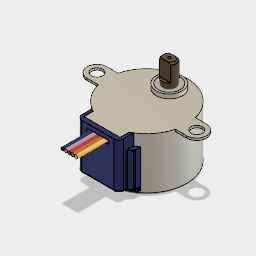
_28BYJ-48+Stepper+Motor.dbc9e391-d2c8-433e-843d-24143737a80f (Autodesk Fusion 360 design; units mm, degrees)
Autodesk Fusion 360 part; units mm, degrees
sketch "24BYJ-48 Step Motor" plane through (0, 0, 0) normal (0, 1, 0) x (1, 0, 0) in component "28BYJ-48 Stepper Motor"
  line L0 (0, 0) -> (0, 7.8573) construction
  circle A0 centre (0, 7.8573) radius 2.5
  circle A1 centre (0, 7.8573) radius 4.6
  line L1 (-2, 9.3573) -> (2, 9.3573)
  line L2 (2, 6.3573) -> (-2, 6.3573)
  circle A2 centre (17.5, -0.0114) radius 2
  arc A3 (17.5, -3.5114) -> (17.5, 3.4886) centre (17.5, -0.0114) ccw
  circle A4 centre (-17.5, -0.0114) radius 2
  arc A5 (-17.5, 3.4886) -> (-17.5, -3.5114) centre (-17.5, -0.0114) ccw
  line L3 (17.5, 3.4886) -> (13.5584, 3.4886)
  line L4 (17.5, -3.5114) -> (13.5525, -3.5114)
  line L5 (-17.5, 3.4886) -> (-13.5584, 3.4886)
  line L6 (-17.5, -3.5114) -> (-13.5525, -3.5114)
  line L7 (-6.3, -12.5024) -> (-6.3, -15.6927)
  line L8 (6.3, -12.5024) -> (6.3, -15.6927)
  line L9 (6.3, -15.6927) -> (-6.3, -15.6927)
  line L10 (7.35, -11.9154) -> (7.35, -15.5438)
  line L11 (5.6511, -17.2427) -> (-5.6511, -17.2427)
  line L12 (-7.35, -15.5438) -> (-7.35, -11.9154)
  arc A6 (-7.35, -15.5438) -> (-5.6511, -17.2427) centre (-5.6511, -15.5438) ccw
  arc A7 (5.6511, -17.2427) -> (7.35, -15.5438) centre (5.6511, -15.5438) ccw
  line L13 (7.35, -14.45) -> (8.75, -13.05)
  line L14 (8.75, -13.05) -> (8.75, -10.9287)
  line L15 (-7.35, -14.45) -> (-8.75, -13.05)
  line L16 (-8.75, -13.05) -> (-8.75, -10.9287)
  line L17 (21, -0.0114) -> (21, 13.9573) construction
  line L18 (-21, -0.0114) -> (-21, 13.9573) construction
  line L19 (21, 13.9573) -> (-21, 13.9573) construction
  circle A8 centre (0, 7.8573) radius 3.85
  line L20 (-6.4707, 3.2573) -> (8.5293, 3.2573) construction
  circle A9 centre (0, 0) radius 14
  arc A10 (-8.75, -11.5623) -> (8.75, -11.5623) centre (0, 0) ccw
  line L21 (-1.5, -14.4222) -> (-1.5, -13.9194)
  line L22 (1.5, -14.4222) -> (1.5, -13.9194)
  dimension "d2" = 3
  dimension "d3" = 5
  dimension "d4" = 3.5
  dimension "d6" = 4
  dimension "d11" = 45
  dimension "d12" = 14.7
  dimension "d14" = 17.5
  dimension "d15" = 12.6
  dimension "d16" = 1.55
  dimension "d17" = 42
  dimension "d18" = 31.2
  dimension "d19" = 9.2
  dimension "d20" = 7.7
  dimension "d21" = 10.7
  dimension "d26" = 28
  dimension "d49" = 14.5
  dimension "d53" = 3
  measures "d2" distance of L1 L2
  measures "d3" diameter of A0
  measures "d4" radius of A3
  measures "d6" diameter of A2
  measures "d11" angle of L10 L13
  measures "d12" distance of L10 L12
  measures "d14" distance of L14 L16
  measures "d15" distance of L7.end L8.end
  measures "d16" distance of L9 L11
  measures "d17" distance of L17 L18
  measures "d18" distance of L11 L19
  measures "d19" diameter of A1
  measures "d20" diameter of A8
  measures "d21" distance of L19 L20
  measures "d26" diameter of A9
  measures "d49" radius of A10
  measures "d53" distance of L21 L22
extrude "Extrude1" add sketch "24BYJ-48 Step Motor" against normal blind 0.75 contours A0 L1 L2 | A0 L1 | A0 L2 | A1 | A3 L3 L4 A9 | A9 | A5 L5 L6 A9 | L8 A9 A10 L22 | L7 L8 L9 A10 | A9 A10 L21 L22 | L7 A9 A10 L21 | A8 makes body 1 in component "Metal Case"
extrude "Extrude2" add sketch "24BYJ-48 Step Motor" against normal blind 19 contours A0 L1 L2 | A0 L1 | A0 L2 | A1 | A9 | A8 bodies 1 in component "Metal Case"
extrude "Extrude3" add sketch "24BYJ-48 Step Motor" along normal blind 1.5 contours A1 bodies 1 in component "Metal Case"
extrude "Extrude1'" add sketch "24BYJ-48 Step Motor" along normal blind 1.5 separate body contours A0 L1 L2 | A0 L1 | A0 L2 | A8 makes body 2 in component "Plastic Base"
extrude "Extrude1''" add sketch "24BYJ-48 Step Motor" along normal blind 3.3 separate body contours A0 L1 L2 | A0 L1 | A0 L2 makes body 3 in component "Metal Rod"
extrude "Extrude2'" add sketch "24BYJ-48 Step Motor" along normal blind 9.3 contours A0 L1 L2 bodies 3 in component "Metal Rod"
extrude "Extrude1'''" add sketch "24BYJ-48 Step Motor" against normal blind 16.5 separate body contours L8 L10 A9 A10 | L7 L8 L9 L10 L11 L12 A6 A7 A10 | L7 L12 A9 A10 makes body 4 in component "Plastic Side"
extrude "Extrude2''" add sketch "24BYJ-48 Step Motor" against normal blind 15.7 from surface at -0.8 contours L8 A9 A10 L22 | L7 L8 L9 A10 | A9 A10 L21 L22 | L7 A9 A10 L21 bodies 4 in component "Plastic Side"
extrude "Extrude3'" add sketch "24BYJ-48 Step Motor" against normal blind 12.5 from surface at -4 contours L10 L14 A9 A10 | L10 L13 L14 A10 | L12 L16 A9 A10 | L12 L15 L16 A10 bodies 4 in component "Plastic Side"
extrude "Extrude4" add sketch "24BYJ-48 Step Motor" against normal blind 1 from surface at -16.5 contours L10 L14 A9 A10 | L8 L10 A9 A10 | L8 A9 A10 L22 | L12 L16 A9 A10 | A9 A10 L21 L22 | L7 L12 A9 A10 | L7 A9 A10 L21 bodies 4 in component "Plastic Side"
fillet "Fillet1" radius 0.5 4 edges at (8.75, -10.25, 13.05) (8.75, -17, 11.5623) (-8.75, -17, 11.5623) (-8.75, -10.25, 13.05) on bodies 4 in component "Plastic Side"
fillet "Fillet3" radius 1 5 edges at (7.35, -16.5, 14.9969) (6.8524, -16.5, 16.7451) (0, -16.5, 17.2427) (-6.8524, -16.5, 16.7451) (-7.35, -16.5, 14.9969) on bodies 4 in component "Plastic Side"
fillet "Fillet4" radius 0.5 10 edges at (8.75, -16.5, 12.0769) (8.7119, -16.5, 13.0342) (7.4768, -16.5, 14.3232) (-7.4768, -16.5, 14.3232) (-8.7119, -16.5, 13.0342) (-8.75, -16.5, 12.0769) (7.0571, -16.2071, 14.7429) (7.35, -9.75, 14.45) (-7.35, -9.75, 14.45) (-7.0571, -16.2071, 14.7429) on bodies 4 in component "Plastic Side"
fillet "Fillet5" radius 0.25 5 edges at (8.75, -17.5, 11.1198) (8.6957, -17.5, 11.5375) (0, -17.5, 14.5) (-8.6957, -17.5, 11.5375) (-8.75, -17.5, 11.1198) on bodies 4 in component "Plastic Side"
fillet "Fillet1'" radius 1 1 edges at (-13.0526, -19, -5.0626) on bodies 1 in component "Metal Case"
sphere "SpherePrimitive1" cut diameter 1 placed x (-1, 0, 0) y (0, 0, 1) z (0, 1, 0) at (0, 9.3, -7.8573) bodies 3 in component "Metal Rod"
sketch "Wires" plane through (0, 0, 17.2427) normal (0, 0, 1) x (1, 0, 0) in component "Wires"
  line L0 (-5.6511, -15.5) -> (5.6511, -15.5)
  line L1 (5.6511, -15.5) -> (5.6511, 0)
  line L2 (5.6511, 0) -> (-5.6511, 0)
  line L3 (-5.6511, 0) -> (-5.6511, -15.5)
  line L4 (0, 0) -> (0, -1.5) construction
  line L5 (3.4, -1.5) -> (-3.4, -1.5)
  line L6 (-3.4, -2.7) -> (3.4, -2.7)
  line L7 (-4, -2.1) -> (4, -2.1) construction
  arc A0 (-3.4, -1.5) -> (-3.4, -2.7) centre (-3.4, -2.1) ccw
  arc A1 (3.4, -2.7) -> (3.4, -1.5) centre (3.4, -2.1) ccw
  circle A2 centre (-2.4, -2.1) radius 0.6
  circle A3 centre (-1.2, -2.1) radius 0.6
  circle A4 centre (0, -2.1) radius 0.6
  circle A5 centre (1.2, -2.1) radius 0.6
  circle A6 centre (2.4, -2.1) radius 0.6
  dimension "d64" = 1.5
  dimension "d66" = 8
  dimension "d67" = 0.6
  measures "d64" distance of L4.start L4.end
  measures "d66" distance of L7.start L7.end
  measures "d67" radius of A1
extrude "Extrude5" cut sketch "Wires" against normal blind 1 contours L5 L6 A1 A6 | L5 A5 A6 | A6 | L5 A4 A5 | A5 | L6 A5 A6 | L5 A3 A4 | A4 | L6 A4 A5 | L5 A2 A3 | A3 | L6 A3 A4 | L5 L6 A0 A2 | A2 | L6 A2 A3 bodies 4 in component "Plastic Side"
extrude "Extrude1''''" add sketch "Wires" along normal blind 10 and the other way blind 1 separate body contours A6 | A5 | A4 | A3 | A2 makes body 5 at (-2.4597, -1.503, 20.2427) in component "Wires"
chamfer "Chamfer1" distance 0.5 angle 45 2 edges at (-2.5, 9.3, -7.8573) (2.5, 9.3, -7.8573) on bodies 3 in component "Metal Rod"
component "28BYJ-48 Stepper Motor" placed x (1, 0, 0) y (0, 1, 0) z (0, 0, 1) at (0, 0, 0)
component "Metal Case" placed x (1, 0, 0) y (0, 1, 0) z (0, 0, 1) at (0, 0, 0) in component "28BYJ-48 Stepper Motor"
component "Plastic Base" placed x (1, 0, 0) y (0, 1, 0) z (0, 0, 1) at (0, 0, 0) in component "Metal Case"
component "Plastic Side" placed x (1, 0, 0) y (0, 1, 0) z (0, 0, 1) at (0, 0, 0) in component "Metal Case"
component "Metal Rod" placed x (1, 0, 0) y (0, 1, 0) z (0, 0, 1) at (0, 0, 0) in component "Plastic Base"
component "Wires" placed x (1, 0, 0) y (0, 1, 0) z (0, 0, 1) at (0, 0, 0) in component "Plastic Side"
equation "d4 = ( 7 / 2 ) * 1 mm"
equation "d39 = 28.5 mm - 19.2 mm"
named bodies: "Metal Case (Motor)", "Plastic Rod Base", "Metal Rod", "Plastic Side", "Wires"
